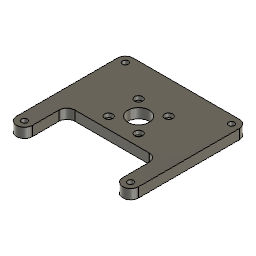
body (Autodesk Fusion 360 archive; units mm, degrees)
design "prop plate"
Autodesk Fusion 360 part; units mm, degrees
sketch "Sketch1" plane through (0, 0, 0) normal (0, 0, 1) x (1, 0, 0)
  circle A0 centre (-20, 15) radius 1.1
  circle A1 centre (20, 15) radius 1.1
  line L0 (20, 15) -> (-20, 15) construction
  circle A2 centre (-20, -23) radius 1.1
  line L1 (-20, 15) -> (-20, -23) construction
  circle A3 centre (20, -23) radius 1.1
  line L2 (20, 15) -> (20, -23) construction
  line L3 (20, -23) -> (-20, -23) construction
  line L4 (5.65, -5.65) -> (-5.65, -5.65) construction
  line L5 (-5.65, -5.65) -> (-5.65, 5.65) construction
  line L6 (-5.65, 5.65) -> (5.65, 5.65) construction
  line L7 (5.65, 5.65) -> (5.65, -5.65) construction
  line L8 (5.65, -5.65) -> (-5.65, 5.65) construction
  line L9 (-5.65, -5.65) -> (5.65, 5.65) construction
  circle A4 centre (-5.65, 5.65) radius 1.5
  circle A5 centre (-5.65, -5.65) radius 1.5
  circle A6 centre (5.65, -5.65) radius 1.5
  circle A7 centre (5.65, 5.65) radius 1.5
  circle A8 centre (0, 0) radius 4
  line L10 (10, 10) -> (-10, 10)
  line L11 (-10, 10) -> (-10, -10)
  line L12 (-10, -10) -> (10, -10)
  line L13 (10, -10) -> (10, 10)
  line L14 (10, 10) -> (-10, -10) construction
  line L15 (-10, 10) -> (10, -10) construction
  line L16 (-20, 18) -> (20, 18)
  line L17 (23, 15) -> (23, -23)
  line L18 (20, -26) -> (-20, -26)
  line L19 (-23, -23) -> (-23, 15)
  line L20 (0, 18) -> (0, 0) construction
  arc A9 (-20, 18) -> (-23, 15) centre (-20, 15) ccw
  arc A10 (23, 15) -> (20, 18) centre (20, 15) ccw
  arc A11 (20, -26) -> (23, -23) centre (20, -23) ccw
  arc A12 (-23, -23) -> (-20, -26) centre (-20, -23) ccw
  line L21 (-17, -26) -> (-17, -10)
  line L22 (17, -26) -> (17, -10)
  line L23 (17, -10) -> (10, -10)
  line L24 (-10, -10) -> (-17, -10)
  point P0 (-23, 18)
  point P1 (23, 18)
  dimension "d1" = 2.2
  dimension "d2" = 20
  dimension "d3" = 2.2
  dimension "d4" = 20
  dimension "d5" = 15
  dimension "d6" = 2.2
  dimension "d7" = 23
  dimension "d8" = 2.2
  dimension "d9" = 11.3
  dimension "d10" = 11.3
  dimension "d11" = 3
  dimension "d13" = 360
  dimension "d14" = 8
  dimension "d15" = 20
  dimension "d16" = 20
  dimension "d17" = 46
  dimension "d19" = 3
  dimension "d20" = 3
  dimension "d21" = 3
  dimension "d22" = 3
  dimension "d23" = 6
  dimension "d24" = 6
  constraint coincident A1.centre L0.start
  constraint coincident A0.centre L0.end
  constraint horizontal L0
  constraint coincident A2.centre L1.end
  constraint vertical L1
  constraint coincident A3.centre L2.end
  constraint vertical L2
  constraint horizontal L3
  constraint horizontal L4
  constraint perpendicular L4 L5
  constraint parallel L4 L6
  constraint parallel L5 L7
  constraint coincident L8 A8.centre
  constraint coincident L9 A8.centre
  constraint coincident A8.centre L20.end
  constraint coincident L5.end L6.start
  constraint horizontal L10
  constraint perpendicular L10 L11
  constraint parallel L10 L12
  constraint parallel L11 L13
  constraint coincident L14 A8.centre
  constraint coincident L15 A8.centre
  constraint horizontal L16
  constraint vertical L17
  constraint horizontal L18
  constraint vertical L19
  constraint vertical L20
  constraint coincident L16 L20.start
  constraint coincident P0 L16
  constraint coincident P0 L19
  constraint tangent L16 A9
  constraint tangent L19 A9
  constraint coincident P1 L16
  constraint coincident P1 L17
  constraint tangent L16 A10
  constraint tangent L17 A10
  constraint equal A9 A10
  constraint tangent L17 A11
  constraint tangent L18 A11
  constraint equal A9 A11
  constraint tangent L18 A12
  constraint tangent L19 A12
  constraint equal A9 A12
  constraint midpoint L16 L20.start
  constraint coincident L18 L21.start
  constraint perpendicular L18 L21
  constraint coincident L18 L22.start
  constraint perpendicular L18 L22
  constraint horizontal L24
  constraint horizontal L23
  measures "d1" diameter of A0
  measures "d2" horizontal distance of A8.centre A0.centre
  measures "d3" diameter of A1
  measures "d4" horizontal distance of A8.centre A1.centre
  measures "d5" distance of A8.centre L0
  measures "d6" diameter of A2
  measures "d7" vertical distance of A8.centre A2.centre
  measures "d8" diameter of A3
  measures "d9" distance of L4.end L5.end
  measures "d10" distance of L5.end L6.end
  measures "d11" diameter of A4
  measures "d14" diameter of A8
  measures "d15" distance of L11.end L12.end
  measures "d16" distance of L10.end L11.end
  measures "d17" distance of P0 P1
  measures "d19" distance of A0.centre L16
  measures "d20" distance of A0.centre L19
  measures "d21" distance of A2.centre L18
  measures "d22" radius of A9
  measures "d23" distance of L17 L22
  measures "d24" distance of L19 L21
extrude "Extrude1" add sketch "Sketch1" along normal blind 3.7 contours L10 L11 L12 L13 | L10 L11 L13 L16 L17 L18 L19 A9 A10 A11 A12 L21 L22 L23 L24
chamfer "Chamfer1" distance 2.2 angle 45 4 edges at (-7.0485, -5.1076, 0) (4.2515, -5.1076, 0) (4.2515, 6.1924, 0) (-7.0485, 6.1924, 0)
fillet "Fillet1" radius 3 4 edges at (17, -10, 1.85) (-17, -10, 1.85) (-17, -26, 1.85) (17, -26, 1.85)
equation "d3 = d1"
equation "d6 = d1"
equation "d8 = d1"
equation "d9 = 14 mm - 2.7 mm"
equation "d10 = d9"
equation "d19 = d20"
equation "d21 = d20"
equation "d24 = d23"
equation "d25 = 0.8 mm + 0.9 mm + 2 mm"
